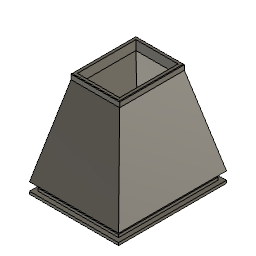
Feeder Hopper (Autodesk Fusion 360 design; units mm, degrees)
part number: 2026-04-26-10-32-45-579
Autodesk Fusion 360 part; units mm, degrees
note: some values were not read from the file. Set by a fixed rule: which face or edge a step refers to.
sketch "Sketch1" plane through (0, 0, 0) normal (0, 0, 1) x (1, 0, 0)
  line L0 (0, 0) -> (33, 0)
  line L1 (33, 0) -> (33, 40)
  line L2 (33, 40) -> (0, 40)
  line L3 (0, 40) -> (0, 0)
  dimension "d1" = 40
  dimension "d2" = 33
  constraint horizontal L0
  constraint vertical L1
  constraint horizontal L2
  constraint vertical L3
  constraint coincident L0.start L3.end
  measures "d1" distance of L0.start L2.end
  measures "d2" distance of L1 L3
ref_plane "WorkPlane1" through (0, 0, 33) normal (0, 0, 1) x (1, 0, 0)
sketch "Sketch2" plane through (0, 0, 33) normal (0, 0, 1) x (1, 0, 0)
  line L0 (0, 40) -> (33, 0) construction
  line L1 (0, 0) -> (33.9117, 38.8949) construction
  circle A0 centre (16.9558, 19.4475) radius 7.5
  line L2 (25.9558, 7.4475) -> (7.9558, 7.4475)
  line L3 (7.9558, 7.4475) -> (7.9558, 31.4475)
  line L4 (7.9558, 31.4475) -> (25.9558, 31.4475)
  line L5 (25.9558, 31.4475) -> (25.9558, 7.4475)
  line L6 (25.9558, 7.4475) -> (7.9558, 31.4475) construction
  line L7 (7.9558, 7.4475) -> (25.9558, 31.4475) construction
  point P0 (16.9558, 19.4475)
  dimension "d4" = 15
  dimension "d15" = 18
  dimension "d16" = 24
  constraint coincident L1.start origin
  constraint midpoint L1 P0
  constraint horizontal L2
  constraint perpendicular L2 L3
  constraint parallel L2 L4
  constraint parallel L3 L5
  constraint coincident L6 P0
  constraint coincident L7 P0
  constraint coincident P0 A0.centre
  measures "d4" diameter of A0
  measures "d15" distance of L3.end L4.end
  measures "d16" distance of L2.end L3.end
loft "Loft1" add profiles "Sketch1", "Sketch2" section 1 section 2 contours A0 | L2 L3 L4 L5 makes body 1
shell "Shell1" thickness 1.5 removed faces 1 at (22, 26.6667, 0) on bodies 1
extrude "Extrude1" cut 1 faces at (19.5406, 15.86, 31.5) along direction (0, 0, 1) blind 8 on bodies 1 bodies 1
extrude "Extrude2" add 1 faces at (25.5513, 15.8472, 33) along direction (0, 0, 1) blind 2 on bodies 1 bodies 1
ref_plane "WorkPlane2" through (0, 0, -6) normal (0, 0, 1) x (1, 0, 0)
sketch "Sketch3" plane through (0, 0, -6) normal (0, 0, 1) x (1, 0, 0)
  line L0 (1.543, 38.4504) -> (1.543, 1.5377)
  line L1 (1.543, 1.5377) -> (31.4662, 1.5377)
  line L2 (31.4662, 1.5377) -> (31.4662, 38.4504)
  line L3 (31.4662, 38.4504) -> (1.543, 38.4504)
  line L4 (0, 0) -> (0, 40)
  line L5 (0, 40) -> (33, 40)
  line L6 (33, 40) -> (33, 0)
  line L7 (33, 0) -> (0, 0)
sketch "Sketch4" plane through (0, 0, -6) normal (0, 0, 1) x (1, 0, 0)
  line L0 (0, 0) -> (33, 0)
  line L1 (33, 0) -> (33, 40)
  line L2 (33, 40) -> (0, 40)
  line L3 (0, 40) -> (0, 0)
  line L4 (31.4, 1.6) -> (1.6, 1.6)
  line L5 (1.6, 1.6) -> (1.6, 38.4)
  line L6 (1.6, 38.4) -> (31.4, 38.4)
  line L7 (31.4, 38.4) -> (31.4, 1.6)
  line L8 (31.4, 1.6) -> (1.6, 38.4) construction
  line L9 (1.6, 1.6) -> (31.4, 38.4) construction
  point P0 (16.5, 20)
  dimension "d17" = 40
  dimension "d18" = 33
  dimension "d19" = 29.8
  dimension "d20" = 36.8
  constraint horizontal L0
  constraint vertical L1
  constraint horizontal L2
  constraint vertical L3
  constraint coincident L0.start L3.end
  constraint horizontal L4
  constraint perpendicular L4 L5
  constraint parallel L4 L6
  constraint parallel L5 L7
  constraint coincident L8 P0
  constraint coincident L9 P0
  measures "d17" distance of L0.start L2.end
  measures "d18" distance of L0.start L0.end
  measures "d19" distance of L5.end L6.end
  measures "d20" distance of L4.end L5.end
extrude "Extrude5" add sketch "Sketch3" against normal blind 1 separate body contours L0 L1 L2 L3 | L4 L5 L6 L7 makes body 2
extrude "Extrude6" add sketch "Sketch4" along normal blind 1 contours L4 L5 L6 L7 bodies 2
fillet "Fillet1" radius 0.2 4 edges at (25.9558, 19.4475, 35) (16.9558, 31.4475, 35) (7.9558, 19.4475, 35) (16.9558, 7.4475, 35) on bodies 1
move_body "Move1" bodies 2 to x (1, 0, 0) y (0, 1, 0) z (0, 0, 1) at (0, 0, 6)
move_body "Move2" bodies 2 to x (1, 0, 0) y (0, 1, 0) z (0, 0, 1) at (0, 0, -3)
